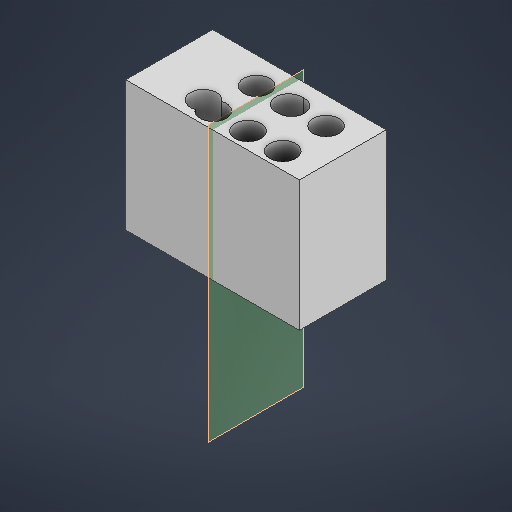
# Autodesk Inventor part: pt_mirror
Saved by Autodesk Inventor 2027 (Build 310192060, 192F)
## iProperties
Created: 2026-10-19
Part Number: pt_mirror
Material: Generic
Document SubType Name: Modeling
Designer: vmiguel
Density: 1 g/cm^3
Appearance: Default
Author: vmiguel
Autodesk Inventor part; units mm, degrees
ref_plane "XZ Plane" through (0, 0, 0) normal (0, 1, 0) x (-1, 0, 0)
ref_plane "XY Plane" through (0, 0, 0) normal (0, 0, 1) x (1, 0, 0)
sketch "Sketch1" plane through (0, 0, 0) normal (0, 0, 1) x (1, 0, 0)
  line L0 (10, 20) -> (50, 20)
  line L1 (50, 20) -> (50, 50)
  line L2 (50, 50) -> (10, 50)
  line L3 (10, 50) -> (10, 20)
  point P0 (0, 0)
  dimension "d0" = 40
  dimension "d1" = 30
  constraints: 8 end point, 2 parallel, 1 horizontal, 1 perpendicular
  measures "d0" distance of L2.end L1.end
  measures "d1" distance of L1.end L0.end
extrude "Extrusion1" add sketch "Sketch1" along normal blind 20
sketch "Sketch2" plane through (10, 50, 0) normal (0, 1, 0) x (1, 0, 0)
  point P0 (-10, 0)
  point P1 (16.3042, -6.152)
hole "Hole1" at (26.3042, 50, 6.152) direction (0, -1, 0) diameter 6 end through all
pattern_linear "Rectangular Pattern1" count 3 spacing 8 along (1, 0, 0) count 2 spacing 10 along (0, 0, 1) of "Hole1"
pattern_circular "Circular Pattern1" count 2 over 20 about axis through (50, 20, 20) along (0, 1, 0) of "Hole1"
ref_plane "Work Plane1" through (30, 0, 0) normal (1, 0, 0) x (0, 1, 0)
mirror "Mirror1" about plane through (30, 0, 0) normal (1, 0, 0) of "Hole1"
ref_plane "Work Plane2" through (30, 0, 0) normal (1, 0, 0) x (0, 1, 0)
body "Solid1"
